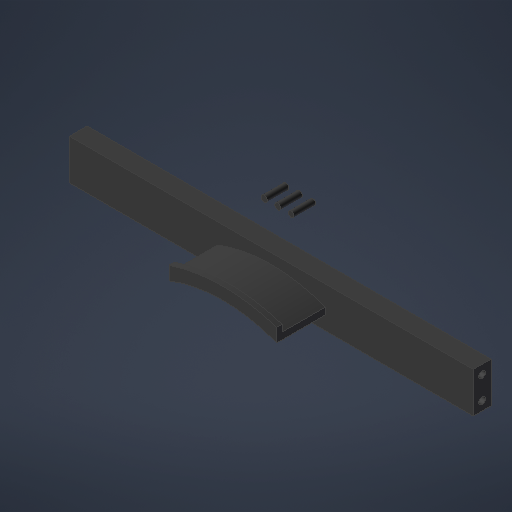
# Autodesk Inventor part: HatStand
Saved by Autodesk Inventor 2026 (Build 300175000, 175)
## iProperties
Created: 2026-03-12
Part Number: HatStand
Material: Generic
Document SubType Name: Modeling
Designer: joshb
Density: 1 g/cm^3
Appearance: Default
Author: joshb
## iProperties of the stored document HatStand_3DPrint.ipt
Created: 2026-03-15
Part Number: HatStand_3DPrint
Material: Generic
Document SubType Name: Modeling
Designer: joshb
Density: 1 g/cm^3
Appearance: Default
Author: joshb
Autodesk Inventor part; units mm, degrees
ref_plane "YZ Plane" through (0, 0, 0) normal (1, 0, 0) x (0, 1, 0)
ref_plane "XZ Plane" through (0, 0, 0) normal (0, 1, 0) x (-1, 0, 0)
ref_plane "XY Plane" through (0, 0, 0) normal (0, 0, 1) x (1, 0, 0)
sketch "Sketch1" plane through (0, 0, 0) normal (0, 0, 1) x (1, 0, 0)
  line L0 (-95.25, -9.525) -> (95.25, -9.525)
  line L1 (95.25, -9.525) -> (95.25, 9.525)
  line L2 (95.25, 9.525) -> (-95.25, 9.525)
  line L3 (-95.25, 9.525) -> (-95.25, -9.525)
  line L4 (-95.25, -9.525) -> (95.25, 9.525) construction
  line L5 (95.25, -9.525) -> (-95.25, 9.525) construction
  point P0 (0, 0)
  dimension "d0" = 190.5
  dimension "d1" = 19.05
  constraints: 12 end point, 2 midpoint, 2 parallel, 1 horizontal, 1 perpendicular
  measures "d0" distance of L1.end L2.end
  measures "d1" distance of L0.end L1.end
extrude "Extrusion1" add sketch "Sketch1" along normal blind 8.382
sketch "Sketch2" plane through (0, 0, 8.382) normal (0, 0, 1) x (1, 0, 0)
  line L0 (-95.25, -9.525) -> (95.25, -9.525) projected
  line L1 (-25.4, 9.525) -> (25.4, 9.525)
  line L2 (25.4, 9.525) -> (25.4, -9.525)
  line L3 (25.4, -9.525) -> (-25.4, -9.525)
  line L4 (-25.4, -9.525) -> (-25.4, 9.525)
  line L5 (-25.4, 9.525) -> (25.4, -9.525) construction
  line L6 (25.4, 9.525) -> (-25.4, -9.525) construction
  arc A0 (25.4, 0) -> (-25.4, 0) centre (0, -65.3521) ccw
  arc A1 (25.4, -3.175) -> (-25.4, -3.175) centre (0, -68.5271) ccw
  point P0 (0, 0)
  constraints: 12 end point, 4 midpoint, 4 point on circle, 3 point on line, 2 centre point, 2 parallel, 1 horizontal, 1 perpendicular
extrude "Extrusion2" add sketch "Sketch2" along normal blind 20.32 contours L4 A0 L2 A1
sketch "Sketch3" plane through (0, 0, 28.702) normal (0, 0, 1) x (1, 0, 0)
  arc A0 (25.4, -3.175) -> (-25.4, -3.175) centre (0, -68.5271) ccw projected
  line L0 (-25.4, -3.175) -> (25.4, -3.175)
  line L1 (25.4, -3.175) -> (25.4, 7.3025)
  line L2 (25.4, 7.3025) -> (-25.4, 7.3025)
  line L3 (-25.4, 7.3025) -> (-25.4, -3.175)
  arc A1 (25.4, -3.175) -> (-25.4, -3.175) centre (0, -68.5271) ccw
  arc A2 (25.4, 3.175) -> (-25.4, 3.175) centre (0, -72.9158) ccw
  point P0 (0, 0)
  constraints: 8 end point, 4 point on circle, 2 centre point, 2 parallel, 2 point on line, 1 concentric, 1 horizontal, 1 perpendicular
extrude "Extrusion3" add sketch "Sketch3" along normal blind 2.54 contours A0 L3 A2 L1
sketch "Sketch4" plane through (95.25, -9.525, 0) normal (1, 0, 0) x (0, 0, -1)
  line L0 (0, 0) -> (-8.382, 0) projected
  line L1 (0, 0) -> (-8.382, 0)
  line L2 (-8.382, 19.05) -> (0, 19.05)
  line L3 (0, 19.05) -> (0, 0)
  line L4 (-8.382, 19.05) -> (-8.382, 10.668)
  line L5 (-8.382, 10.668) -> (0, 10.668)
  line L6 (0, 19.05) -> (-8.382, 19.05)
  line L7 (-8.382, 0) -> (0, 0)
  line L8 (0, 0) -> (0, 8.382)
  line L9 (0, 8.382) -> (-8.382, 8.382)
  line L10 (-8.382, 8.382) -> (-8.382, 0)
  circle A0 centre (-4.191, 4.191) radius 1.5875
  circle A1 centre (-4.191, 14.859) radius 1.5875
  point P0 (0, 9.525)
  dimension "d10" = 8.382
  dimension "d11" = 8.382
  dimension "d12" = 3.175
  constraints: 20 end point, 4 equal length, 2 centre point, 2 horizontal, 2 perpendicular, 2 point on line
  measures "d10" distance of L2.start L4.end
  measures "d11" distance of L9.end L0.end
  measures "d12" diameter of A0
extrude "Extrusion4" cut sketch "Sketch4" against normal blind 6.35 contours A0 | A1
sketch "Sketch5" plane through (-95.25, -9.525, 0) normal (-1, 0, 0) x (0, 0, 1)
  line L0 (0, 0) -> (8.382, 0) projected
  line L1 (0, 0) -> (0, 19.05) projected
  line L2 (8.382, 0) -> (0, 0)
  line L3 (0, 0) -> (0, 8.382)
  line L4 (0, 8.382) -> (8.382, 8.382)
  line L5 (8.382, 8.382) -> (8.382, 0)
  line L6 (0, 19.05) -> (8.382, 19.05)
  line L7 (8.382, 19.05) -> (8.382, 10.668)
  line L8 (8.382, 10.668) -> (0, 10.668)
  line L9 (0, 10.668) -> (0, 19.05)
  circle A0 centre (4.191, 14.859) radius 1.5875
  circle A1 centre (4.191, 4.191) radius 1.5875
  point P0 (0, 9.525)
  dimension "d15" = 8.382
  dimension "d16" = 8.382
  constraints: 16 end point, 4 parallel, 2 centre point, 2 horizontal, 2 perpendicular, 1 point on line
  measures "d15" distance of L4.end L0.end
  measures "d16" distance of L6.end L7.end
extrude "Extrusion5" cut sketch "Sketch5" against normal blind 6.35 contours A0 | A1
sketch "Sketch6" plane through (0, 0, 0) normal (0, 0, -1) x (-1, 0, 0)
  circle A0 centre (1.5875, 31.75) radius 1.4605
  circle A1 centre (-4.7625, 31.75) radius 1.4605
  circle A2 centre (-11.1125, 31.75) radius 1.397
  point P0 (0, 0)
  dimension "d21" = 2.921
  dimension "d22" = 2.921
  dimension "d23" = 2.794
  constraints: 3 centre point
  measures "d21" diameter of A0
  measures "d22" diameter of A1
  measures "d23" diameter of A2
extrude "Extrusion6" add sketch "Sketch6" against normal blind 10.16
body "Solid1"
